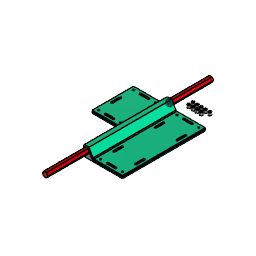
RC_CAR_frame2.0 (Autodesk Fusion 360 design; units mm, degrees)
Autodesk Fusion 360 part; units mm, degrees
sketch "support_frame" plane through (0, 0, 0) normal (0, 1, 0) x (1, 0, 0)
  line L0 (2.5, 4.3301) -> (-2.5, 4.3301)
  line L1 (-2.5, 4.3301) -> (-5, 0)
  line L2 (-5, 0) -> (-2.5, -4.3301)
  line L3 (-2.5, -4.3301) -> (2.5, -4.3301)
  line L4 (2.5, -4.3301) -> (5, 0)
  line L5 (5, 0) -> (2.5, 4.3301)
  dimension "d1" = 5
  constraint horizontal L3
  measures "d1" distance of L2.end L3.end
extrude "Extrude1" add sketch "support_frame" along normal blind 0 and the other way blind 300 makes body 1
sketch "TOP_frame" plane through (0, 0, 0) normal (0, 1, 0) x (-1, 0, 0)
  line L0 (-5, 0) -> (-2.5, -4.3301)
  line L1 (-2.5, -4.3301) -> (2.5, -4.3301)
  line L2 (2.5, -4.3301) -> (5, 0)
  line L3 (5, 0) -> (2.5, 4.3301)
  line L4 (2.5, 4.3301) -> (-2.5, 4.3301)
  line L5 (-2.5, 4.3301) -> (-5, 0)
  line L6 (8.5218, 0) -> (4.2609, 7.3801)
  line L7 (4.2609, 7.3801) -> (-4.2609, 7.3801)
  line L8 (-4.2609, 7.3801) -> (-8.5218, 0)
  line L9 (5.0577, 0) -> (2.5289, 4.3801)
  line L10 (2.5289, 4.3801) -> (-2.5289, 4.3801)
  line L11 (-2.5289, 4.3801) -> (-5.0577, 0)
  line L12 (-5.0577, 0) -> (-2.5289, -4.3801)
  line L13 (-2.5289, -4.3801) -> (2.5289, -4.3801)
  line L14 (2.5289, -4.3801) -> (5.0577, 0)
  line L15 (8.5218, 0) -> (11.0507, -4.3801)
  line L16 (0, -4.3801) -> (0, -6.5801) construction
  line L17 (11.0507, -4.3801) -> (11.7435, -5.5801)
  line L18 (-8.5218, 0) -> (-11.7435, -5.5801)
  line L19 (-13.4756, -6.5801) -> (-65, -6.5801)
  line L20 (13.4756, -6.5801) -> (65, -6.5801)
  line L21 (65, -6.5801) -> (65, -11.5801)
  line L22 (-65, -6.5801) -> (-65, -11.5801)
  line L23 (-65, -11.5801) -> (65, -11.5801)
  line L24 (65, -9.0801) -> (56, -9.0801)
  line L25 (5.0577, 0) -> (14.3528, 0) construction
  line L26 (5.0577, 0) -> (9.5785, -7.8301)
  line L27 (56, -9.0801) -> (11.7435, -9.0801)
  line L28 (-5.0577, 0) -> (-9.5785, -7.8301)
  line L29 (-11.7435, -9.0801) -> (-65, -9.0801)
  arc A0 (11.7435, -5.5801) -> (13.4756, -6.5801) centre (13.4756, -4.5801) ccw
  arc A1 (9.5785, -7.8301) -> (11.7435, -9.0801) centre (11.7435, -6.5801) ccw
  arc A2 (-11.7435, -9.0801) -> (-9.5785, -7.8301) centre (-11.7435, -6.5801) ccw
  arc A3 (-13.4756, -6.5801) -> (-11.7435, -5.5801) centre (-13.4756, -4.5801) ccw
  line L30 (5, -15) -> (65, -15)
  line L31 (65, -15) -> (65, 9)
  line L32 (65, 9) -> (5, 9)
  line L33 (5, 9) -> (5, -15)
  line L34 (-2.5, -4.3301) -> (2.5, -4.3301)
  line L35 (-5.1155, 0) -> (-2.5577, -4.4301)
  line L36 (-2.5577, -4.4301) -> (2.5577, -4.4301)
  line L37 (2.5577, -4.4301) -> (5.1155, 0)
  line L38 (5.1155, 0) -> (2.5577, 4.4301)
  line L39 (2.5577, 4.4301) -> (-2.5577, 4.4301)
  line L40 (-2.5577, 4.4301) -> (-5.1155, 0)
  dimension "d9" = 0.05
  dimension "d10" = 3
  dimension "d19" = 2.2
  dimension "d21" = 60
  dimension "d23" = 60
  dimension "d24" = 5
  dimension "d25" = 5
  dimension "d26" = 2.5
  dimension "d30" = 2
  dimension "d31" = 2.5
  dimension "d32" = 2.5
  dimension "d33" = 2
  dimension "d134" = 0.05
  dimension "d135" = 0.1
  constraint horizontal L7
  constraint horizontal L10
  constraint midpoint L13 L16.start
  constraint perpendicular L13 L16
  constraint parallel L8 L18
  constraint horizontal L19
  constraint horizontal L20
  constraint perpendicular L20 L21
  constraint perpendicular L19 L22
  constraint perpendicular L21 L23
  constraint coincident L21 L24.start
  constraint perpendicular L21 L24
  constraint horizontal L25
  constraint midpoint L22 L29.end
  constraint parallel L5 L28
  constraint tangent L17 A0
  constraint tangent L20 A0
  constraint tangent L27 A1
  constraint tangent L26 A1
  constraint tangent L28 A2
  constraint tangent L29 A2
  constraint tangent L18 A3
  constraint tangent L19 A3
  constraint horizontal L30
  constraint vertical L31
  constraint horizontal L32
  constraint vertical L33
  constraint horizontal L36
  measures "d9" distance of L4 L10
  measures "d10" distance of L7 L10
  measures "d19" distance of L16.start L16.end
  measures "d21" horizontal distance of L2.end L20.end
  measures "d23" horizontal distance of L0.start L19.end
  measures "d24" distance of L20.end L21.end
  measures "d25" distance of L19.end L22.end
  measures "d26" distance of L23 L24
  measures "d30" radius of A0
  measures "d31" radius of A1
  measures "d32" radius of A2
  measures "d33" radius of A3
  measures "d134" distance of L13 L34
  measures "d135" distance of L34 L36
extrude "Extrude2" cut 1 faces at (0.8333, -300, -1.4434) along direction (0, 1, 0) blind 150 on bodies 1 bodies 1
extrude "Extrude3" add sketch "TOP_frame" against normal blind 150 separate body contours L12 L13 L14 L28 L33 L35 L36 L37 | L14 L26 L33 L37 | L21 L23 L24 L26 L27 A1 L31 L33 L37 | L22 L23 L28 L29 A2 L33 L35 L36 L37 makes body 2
extrude "Extrude4" add sketch "TOP_frame" against normal blind 150 separate body contours L9 L26 L33 L37 L38 | L9 L10 L11 L28 L33 L35 L38 L39 L40 | L6 L7 L8 L18 L19 L22 L28 L29 A2 A3 L33 L35 L38 L39 L40 | L6 L15 L17 L20 L21 L24 L26 L27 A0 A1 L31 L33 L37 L38 makes body 3
extrude "Extrude5" add sketch "TOP_frame" along normal blind 75 contours L0 L1 L2 L3 L4 L5 L34 bodies 1
extrude "Extrude6" add 1 faces at (0.8333, -150, -1.4434) along direction (0, -1, 0) blind 75 on bodies 1 bodies 1
extrude "Extrude7" cut sketch "TOP_frame" against normal blind 150 from surface at -75 contours L9 L26 L33 L37 L38 | L14 L26 L33 L37 | L6 L15 L17 L20 L21 L24 L26 L27 A0 A1 L31 L33 L37 L38 | L21 L23 L24 L26 L27 A1 L31 L33 L37 bodies 2 3
sketch "Screw_frame" plane through (0, 0, -11.5801) normal (0, 0, -1) x (1, 0, 0)
  line L0 (-5, 150) -> (-5, 75)
  line L1 (-5, 75) -> (-65, 75)
  line L2 (-65, 75) -> (-65, 0)
  line L3 (-65, 0) -> (65, 0)
  line L4 (65, 0) -> (65, 150)
  line L5 (65, 150) -> (-5, 150)
  line L6 (65, 0) -> (-65, 0)
  circle A0 centre (-59, 69) radius 1.6
  circle A1 centre (-59, 6) radius 1.6
  line L7 (-5, 0) -> (-65, 0)
  circle A2 centre (-19.5, 6) radius 1.6
  circle A3 centre (-19.5, 69) radius 1.6
  circle A4 centre (59, 6) radius 1.6
  circle A5 centre (59, 144) radius 1.6
  line L8 (13.5, 0) -> (13.5, 150)
  circle A6 centre (19.5, 144) radius 1.6
  circle A7 centre (19.5, 6) radius 1.6
  dimension "d47" = 130
  dimension "d48" = 60
  dimension "d49" = 150
  dimension "d50" = 3.2
  dimension "d52" = 6
  dimension "d53" = 6
  dimension "d54" = 3.2
  dimension "d55" = 6
  dimension "d56" = 6
  dimension "d58" = 3.2
  dimension "d59" = 6
  dimension "d61" = 3.2
  dimension "d62" = 6
  dimension "d64" = 3.2
  dimension "d65" = 6
  dimension "d66" = 6
  dimension "d67" = 3.2
  dimension "d68" = 6
  dimension "d69" = 6
  dimension "d70" = 138
  dimension "d71" = 51.5
  dimension "d72" = 3.2
  dimension "d73" = 6
  dimension "d74" = 6
  dimension "d75" = 3.2
  dimension "d76" = 6
  dimension "d77" = 6
  constraint coincident L3 L8.start
  constraint coincident L5 L8.end
  constraint perpendicular L5 L8
  measures "d47" distance of L3.end L2.end
  measures "d48" distance of L0.end L1.end
  measures "d49" distance of L3.end L4.end
  measures "d50" diameter of A0
  measures "d52" distance of L2 A0.centre
  measures "d53" distance of L1 A0.centre
  measures "d54" diameter of A1
  measures "d55" distance of L2 A1.centre
  measures "d56" distance of A1.centre L7
  measures "d58" diameter of A2
  measures "d59" distance of L7 A2.centre
  measures "d61" diameter of A3
  measures "d62" distance of L1 A3.centre
  measures "d64" diameter of A4
  measures "d65" distance of L4 A4.centre
  measures "d66" distance of L6 A4.centre
  measures "d67" diameter of A5
  measures "d68" distance of L5 A5.centre
  measures "d69" distance of L4 A5.centre
  measures "d70" distance of A4.centre A5.centre
  measures "d71" distance of L4 L8
  measures "d72" diameter of A6
  measures "d73" distance of L8 A6.centre
  measures "d74" distance of L5 A6.centre
  measures "d75" diameter of A7
  measures "d76" distance of L6 A7.centre
  measures "d77" distance of L8 A7.centre
extrude "Extrude8" cut sketch "Screw_frame" against normal blind 5 contours A0 | A1 | A2 | A3 | A4 | A5 | A6 | A7 bodies 2 3
sketch "Sketch5" plane through (0, 0, -11.5801) normal (0, 0, -1) x (1, 0, 0)
  line L0 (-5, 150) -> (-5, 75)
  line L1 (-5, 75) -> (-65, 75)
  line L2 (-65, 75) -> (-65, 0)
  line L3 (-65, 0) -> (65, 0)
  line L4 (65, 0) -> (65, 150)
  line L5 (65, 150) -> (-5, 150)
  circle A0 centre (59, 6) radius 1.6
  circle A1 centre (-19.5, 6) radius 1.6
  circle A2 centre (-59, 6) radius 1.6
  circle A3 centre (19.5, 6) radius 1.6
  circle A4 centre (59, 144) radius 1.6
  circle A5 centre (-19.5, 69) radius 1.6
  circle A6 centre (-59, 69) radius 1.6
  circle A7 centre (19.5, 144) radius 1.6
  line L6 (-31.75, 4.4) -> (-46.75, 4.4)
  line L7 (-31.75, 7.6) -> (-46.75, 7.6)
  arc A8 (-46.75, 7.6) -> (-46.75, 4.4) centre (-46.75, 6) ccw
  arc A9 (-31.75, 4.4) -> (-31.75, 7.6) centre (-31.75, 6) ccw
  line L8 (-69, 37.5) -> (5, 37.5) construction
  line L9 (-31.75, 70.6) -> (-46.75, 70.6)
  arc A10 (-46.75, 70.6) -> (-46.75, 67.4) centre (-46.75, 69) ccw
  line L10 (-31.75, 67.4) -> (-46.75, 67.4)
  arc A11 (-31.75, 67.4) -> (-31.75, 70.6) centre (-31.75, 69) ccw
  line L11 (-57.4195, 45.0072) -> (-57.407, 29.9088)
  arc A12 (-60.5954, 30.029) -> (-57.407, 29.9088) centre (-59, 30) ccw
  line L12 (-60.5563, 44.7245) -> (-60.5954, 30.029)
  arc A13 (-57.4195, 45.0072) -> (-60.5563, 44.7245) centre (-59, 45) ccw
  line L13 (-59, 30) -> (-59, 37.5)
  line L14 (46.7432, 4.4) -> (31.75, 4.4)
  arc A14 (31.75, 7.6) -> (31.75, 4.4) centre (31.75, 6) ccw
  line L15 (46.7568, 7.6) -> (31.75, 7.6)
  arc A15 (46.7432, 4.4) -> (46.7568, 7.6) centre (46.75, 6) ccw
  line L16 (31.75, 6) -> (39.25, 6)
  line L17 (71, 75) -> (-5, 75) construction
  line L18 (46.7568, 142.4) -> (31.75, 142.4)
  arc A16 (31.75, 145.6) -> (31.75, 142.4) centre (31.75, 144) ccw
  line L19 (46.7432, 145.6) -> (31.75, 145.6)
  arc A17 (46.7568, 142.4) -> (46.7432, 145.6) centre (46.75, 144) ccw
  line L20 (0, -16) -> (0, 164) construction
  line L21 (0, -16) -> (0, 164) construction
  line L22 (60.5563, 44.7245) -> (60.5954, 30.029)
  arc A18 (60.5563, 44.7245) -> (57.4195, 45.0072) centre (59, 45) ccw
  line L23 (57.4195, 45.0072) -> (57.407, 29.9088)
  arc A19 (57.407, 29.9088) -> (60.5954, 30.029) centre (59, 30) ccw
  line L24 (60.5563, 105.2755) -> (60.5954, 119.971)
  line L25 (57.4195, 104.9928) -> (57.407, 120.0912)
  arc A20 (60.5954, 119.971) -> (57.407, 120.0912) centre (59, 120) ccw
  arc A21 (57.4195, 104.9928) -> (60.5563, 105.2755) centre (59, 105) ccw
  line L26 (39.25, 162) -> (39.2502, -10.882) construction
  line L27 (17.9439, 44.7244) -> (17.9049, 30.029)
  arc A22 (21.0807, 45.0072) -> (17.9439, 44.7244) centre (19.5002, 45) ccw
  arc A23 (17.9049, 30.029) -> (21.0932, 29.9088) centre (19.5002, 30) ccw
  line L28 (21.0807, 45.0072) -> (21.0932, 29.9088)
  line L29 (21.0806, 104.9927) -> (21.0931, 120.0912)
  line L30 (17.9437, 105.2755) -> (17.9047, 119.9709)
  arc A24 (21.0931, 120.0912) -> (17.9047, 119.9709) centre (19.5, 120) ccw
  arc A25 (17.9437, 105.2755) -> (21.0806, 104.9927) centre (19.5001, 105) ccw
  dimension "d80" = 39.5
  dimension "d81" = 3.2
  dimension "d82" = 3.2
  dimension "d83" = 15
  dimension "d86" = 37.5
  dimension "d87" = 37.5
  dimension "d88" = 6
  dimension "d89" = 15
  dimension "d90" = 7.5
  dimension "d91" = 37.5
  dimension "d92" = 3.2
  dimension "d93" = 3.2
  dimension "d94" = 15
  dimension "d95" = 7.5
  dimension "d96" = 39.5
  dimension "d97" = 19.75
  dimension "d98" = 6
  dimension "d99" = 6
  dimension "d100" = 150
  dimension "d101" = 75
  dimension "d102" = 65
  dimension "d103" = 6
  dimension "d105" = 6
  dimension "d106" = 69
  dimension "d117" = 19.75
  dimension "d118" = 19.75
  dimension "d119" = 39.5
  constraint tangent L6 A8
  constraint tangent L7 A8
  constraint perpendicular L2 L8
  constraint symmetric L6.start L8 L9.start
  constraint symmetric L6.end L8 L9.end
  constraint symmetric L7.start L8 L10.start
  constraint symmetric L7.end L8 A10.end
  constraint symmetric A8 L8 A10
  constraint symmetric A9 L8 A11
  constraint coincident A12.centre L13.start
  constraint vertical L13
  constraint tangent L14 A14
  constraint tangent A14 L15
  constraint coincident A14.centre L16.start
  constraint parallel L14 L16
  constraint perpendicular L4 L17
  constraint symmetric L14.start L17 L19.start
  constraint symmetric L14.end L17 A16.start
  constraint symmetric L15.start L17 L18.start
  constraint symmetric A14.start L17 L18.end
  constraint symmetric A14 L17 A16
  constraint symmetric A15 L17 A17
  constraint vertical L20
  constraint symmetric L11.start L20 A18.end
  constraint symmetric A12.start L20 L22.end
  constraint symmetric L11.end L20 L23.end
  constraint symmetric L12.start L20 L22.start
  constraint symmetric A12 L20 A19
  constraint symmetric A13 L20 A18
  constraint symmetric L21.start L20 L20.start
  constraint symmetric L21.end L20 L20.end
  constraint symmetric L17 L22.start L24.start
  constraint symmetric L17 L22.end L24.end
  constraint symmetric L17 A18.end L25.start
  constraint symmetric L17 A18 A21
  constraint symmetric L17 L23.end L25.end
  constraint symmetric L17 A19 A20
  constraint perpendicular L14 L26
  constraint vertical L26
  constraint symmetric L22.start L26 L27.start
  constraint symmetric L22.end L26 L27.end
  constraint symmetric A18.end L26 A22.start
  constraint symmetric A18 L26 A22
  constraint symmetric L23.end L26 A23.end
  constraint symmetric A19 L26 A23
  constraint symmetric L24.start L26 L30.start
  constraint symmetric L24.end L26 L30.end
  constraint symmetric L25.start L26 L29.start
  constraint symmetric L25.end L26 L29.end
  constraint symmetric A20 L26 A24
  constraint symmetric A21 L26 A25
  measures "d80" distance of A1.centre A2.centre
  measures "d81" diameter of A8
  measures "d82" diameter of A9
  measures "d83" distance of A8.centre A9.centre
  measures "d86" distance of L3 L8
  measures "d87" distance of L1 L8
  measures "d88" distance of L2 A12.centre
  measures "d89" vertical distance of A13.centre A12.centre
  measures "d90" distance of A12.centre L13.end
  measures "d91" distance of L3 L13.end
  measures "d92" diameter of A14
  measures "d93" diameter of A15
  measures "d94" distance of A14.centre A15.centre
  measures "d95" distance of A14.centre L16.end
  measures "d96" distance of A0.centre A3.centre
  measures "d97" distance of A3.centre L16.end
  measures "d98" distance of L3 A15.centre
  measures "d99" distance of L3 A14.centre
  measures "d100" distance of L3.end L4.end
  measures "d101" distance of L3 L17
  measures "d102" distance of L4 L20
  measures "d103" distance of L4 A19.centre
  measures "d105" distance of L2 A12.centre
  measures "d106" distance of A0.centre L17
  measures "d117" distance of A7.centre L26
  measures "d118" distance of A4.centre L26
  measures "d119" distance of A4.centre A7.centre
extrude "Extrude9" cut sketch "Sketch5" against normal blind 5 contours L6 L7 A8 A9 | L9 A10 L10 A11 | L11 A12 L12 A13 | L14 A14 L15 A15 | L18 A16 L19 A17 | L22 A18 L23 A19 | L24 L25 A20 A21 bodies 2 3
sketch "Sketch7" plane through (0, 0, 0) normal (0, 0, 1) x (1, 0, 0)
  circle A0 centre (20, 15) radius 2.75
  circle A1 centre (20, 15) radius 1.6
  circle A2 centre (27.5, 15) radius 2.75
  circle A3 centre (27.5, 15) radius 1.6
  circle A4 centre (20, 22.5) radius 2.75
  circle A5 centre (20, 22.5) radius 1.6
  circle A6 centre (27.5, 22.5) radius 2.75
  circle A7 centre (27.5, 22.5) radius 1.6
  circle A8 centre (35, 15) radius 1.6
  circle A9 centre (35, 15) radius 2.75
  circle A10 centre (42.5, 15) radius 2.75
  circle A11 centre (42.5, 15) radius 1.6
  circle A12 centre (42.5, 22.5) radius 2.75
  circle A13 centre (42.5, 22.5) radius 1.6
  circle A14 centre (35, 22.5) radius 2.75
  circle A15 centre (35, 22.5) radius 1.6
  circle A16 centre (50.5, 22.5) radius 2.75
  circle A17 centre (50.5, 22.5) radius 1.6
  dimension "d109" = 5.5
  dimension "d110" = 3.2
  dimension "d111" = 5.5
  dimension "d112" = 3.2
  dimension "d113" = 5.5
  dimension "d114" = 3.2
  dimension "d115" = 5.5
  dimension "d116" = 3.2
  dimension "d122" = 5.5
  dimension "d123" = 3.2
  dimension "d124" = 5.5
  dimension "d125" = 3.2
  dimension "d126" = 5.5
  dimension "d127" = 3.2
  dimension "d128" = 5.5
  dimension "d129" = 3.2
  dimension "d130" = 5.5
  dimension "d131" = 3.2
  constraint concentric A0 A1
  constraint concentric A2 A3
  constraint concentric A4 A5
  constraint concentric A6 A7
  constraint concentric A8 A9
  constraint concentric A10 A11
  constraint concentric A14 A15
  constraint concentric A12 A13
  constraint concentric A16 A17
  measures "d109" diameter of A0
  measures "d110" diameter of A1
  measures "d111" diameter of A2
  measures "d112" diameter of A3
  measures "d113" diameter of A4
  measures "d114" diameter of A5
  measures "d115" diameter of A6
  measures "d116" diameter of A7
  measures "d122" diameter of A9
  measures "d123" diameter of A8
  measures "d124" diameter of A10
  measures "d125" diameter of A11
  measures "d126" diameter of A14
  measures "d127" diameter of A15
  measures "d128" diameter of A12
  measures "d129" diameter of A13
  measures "d130" diameter of A16
  measures "d131" diameter of A17
extrude "Extrude10" cut sketch "Sketch5" against normal blind 5 contours L27 A22 A23 L28 | L29 L30 A24 A25 bodies 2 3
extrude "Extrude11" add sketch "Sketch7" against normal blind 5 separate body makes body 4 at (45.2466, 14.8629, -3.3333) makes body 5 at (30.2466, 14.8629, -3.3333) makes body 6 at (22.7466, 14.8629, -3.3333) makes body 7 at (37.7466, 22.3629, -3.3333) makes body 8 at (45.2466, 22.3629, -3.3333) makes body 9 at (30.2466, 22.3629, -3.3333) makes body 10 at (22.7466, 22.3629, -3.3333) makes body 11 at (37.7466, 14.8629, -3.3333) makes body 12 at (53.2466, 22.3629, -3.3333)
sketch "Sketch8" plane through (0, 0, -11.5801) normal (0, 0, -1) x (1, 0, 0)
  line L0 (57.407, 29.9088) -> (57.4195, 45.0072)
  arc A0 (60.5563, 44.7245) -> (57.4195, 45.0072) centre (59, 45) ccw
  line L1 (60.5563, 44.7245) -> (60.5954, 30.029)
  arc A1 (57.407, 29.9088) -> (60.5954, 30.029) centre (59, 30) ccw
  line L2 (-46.75, 7.6) -> (-31.75, 7.6)
  arc A2 (-31.75, 4.4) -> (-31.75, 7.6) centre (-31.75, 6) ccw
  line L3 (-31.75, 4.4) -> (-46.75, 4.4)
  arc A3 (-46.75, 7.6) -> (-46.75, 4.4) centre (-46.75, 6) ccw
  line L4 (31.75, 7.6) -> (46.7568, 7.6)
  arc A4 (46.7432, 4.4) -> (46.7568, 7.6) centre (46.75, 6) ccw
  line L5 (46.7432, 4.4) -> (31.75, 4.4)
  arc A5 (31.75, 7.6) -> (31.75, 4.4) centre (31.75, 6) ccw
  line L6 (60.5954, 119.971) -> (60.5563, 105.2755)
  arc A6 (57.4195, 104.9928) -> (60.5563, 105.2755) centre (59, 105) ccw
  line L7 (57.4195, 104.9928) -> (57.407, 120.0912)
  arc A7 (60.5954, 119.971) -> (57.407, 120.0912) centre (59, 120) ccw
  line L8 (-60.5954, 30.029) -> (-60.5563, 44.7245)
  arc A8 (-57.4195, 45.0072) -> (-60.5563, 44.7245) centre (-59, 45) ccw
  line L9 (-57.4195, 45.0072) -> (-57.407, 29.9088)
  arc A9 (-60.5954, 30.029) -> (-57.407, 29.9088) centre (-59, 30) ccw
  line L10 (-46.75, 70.6) -> (-31.75, 70.6)
  arc A10 (-31.75, 67.4) -> (-31.75, 70.6) centre (-31.75, 69) ccw
  line L11 (-31.75, 67.4) -> (-46.75, 67.4)
  arc A11 (-46.75, 70.6) -> (-46.75, 67.4) centre (-46.75, 69) ccw
  line L12 (31.75, 145.6) -> (46.7432, 145.6)
  arc A12 (46.7568, 142.4) -> (46.7432, 145.6) centre (46.75, 144) ccw
  line L13 (46.7568, 142.4) -> (31.75, 142.4)
  arc A13 (31.75, 145.6) -> (31.75, 142.4) centre (31.75, 144) ccw
  line L14 (-5, 150) -> (-5, 75)
  line L15 (-5, 75) -> (-65, 75)
  line L16 (-65, 75) -> (-65, 0)
  line L17 (-65, 0) -> (65, 0)
  line L18 (65, 0) -> (65, 150)
  line L19 (65, 150) -> (-5, 150)
  circle A14 centre (59, 6) radius 1.6
  circle A15 centre (-19.5, 6) radius 1.6
  circle A16 centre (-59, 6) radius 1.6
  circle A17 centre (19.5, 6) radius 1.6
  circle A18 centre (59, 144) radius 1.6
  circle A19 centre (-19.5, 69) radius 1.6
  circle A20 centre (-59, 69) radius 1.6
  circle A21 centre (19.5, 144) radius 1.6
  line L20 (21.0931, 120.0912) -> (21.0806, 104.9927)
  arc A22 (17.9437, 105.2755) -> (21.0806, 104.9927) centre (19.5001, 105) ccw
  line L21 (17.9437, 105.2755) -> (17.9047, 119.9709)
  arc A23 (21.0931, 120.0912) -> (17.9047, 119.9709) centre (19.5, 120) ccw
  arc A24 (17.9049, 30.029) -> (21.0932, 29.9088) centre (19.5002, 30) ccw
  line L22 (17.9049, 30.029) -> (17.9439, 44.7244)
  arc A25 (21.0807, 45.0072) -> (17.9439, 44.7244) centre (19.5002, 45) ccw
  line L23 (21.0807, 45.0072) -> (21.0932, 29.9088)
extrude "Extrude12" cut sketch "TOP_frame" against normal blind 200 contours L9 L26 L33 L37 L38 | L9 L10 L11 L28 L33 L35 L38 L39 L40 | L12 L13 L14 L28 L33 L35 L36 L37 | L14 L26 L33 L37 bodies 2 3
equation "d86 = ( 75 / 2 ) * 1 mm"
equation "d97 = ( 39.5 / 2 ) * 1 mm"
equation "d117 = ( 39.50 / 2 ) * 1 mm"
named bodies: "TOP_MOUNT", "BOTTOM_MOUNT"
